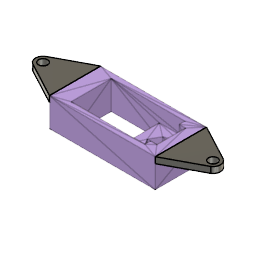
servo box (Autodesk Fusion 360 design; units mm, degrees)
part number: 2026-03-12-15-12-55-324
Autodesk Fusion 360 part; units mm, degrees
other "Base Mesh Feature1"
sketch "Sketch1" plane through (0, 0, 0) normal (0, 0, 1) x (1, 0, 0)
other "Scale1"
other "Modify1"
sketch "Sketch2" plane through (0, 0, 0) normal (0, 0, 1) x (1, 0, 0)
  line L0 (0, 0) -> (0, 16)
  circle A0 centre (10, 8) radius 1.4
  line L1 (0, 0) -> (11.31, 6.032)
  line L2 (11.31, 9.968) -> (0, 16)
  arc A1 (10.9046, 5.8158) -> (10.9046, 10.1842) centre (10, 8) ccw
  line L3 (-45.3729, 8) -> (-43.02, 8)
  circle A2 centre (-43.02, 8) radius 1.4
  line L4 (-33.02, 0) -> (-44.1273, 5.9239)
  line L5 (-44.1273, 10.0761) -> (-33.02, 16)
  line L6 (-33.02, 16) -> (-33.02, 0)
  arc A3 (-44.1273, 10.0761) -> (-44.1273, 5.9239) centre (-43.02, 8) ccw
  dimension "d5" = 2.8
  dimension "d8" = 2.8
  constraint coincident L0.start L1.start
  constraint concentric A0 A1
  constraint coincident L1.end A1
  constraint coincident L2.start A1
  constraint coincident L2 A1.end
  constraint coincident L1 A1.start
  constraint coincident L3.end A2.centre
  constraint concentric A2 A3
  constraint tangent L4 A3
  constraint coincident L3.start A3
  constraint vertical L6
  measures "d5" diameter of A0
  measures "d8" diameter of A2
extrude "Extrude1" add sketch "Sketch2" along normal blind 9 contours L0 L1 L2 A1 | L4 L5 L6 A3 makes body 1 at (0, 10.6666, 6) makes body 2 at (-33.02, 5.3333, 6)
extrude "Extrude2" cut 2 faces at (2.8667, 8, 0) (-35.8867, 8, 0) along direction (0, 0, 1) blind 7.112 on bodies 1 2 bodies 1 2
